Autodesk Fusion 360 part; units mm, degrees
(part 4 of 8)
sketch "F Mount Holes" plane through (-20.5061, -20.5061, 0) normal (0.707107, 0.707107, 0) x (0, 0, 1) in component "F Metal Hub Adapter"
  circle A0 centre (22.6274, 22.6274) radius 2.15
  circle A1 centre (-22.6274, 22.6274) radius 2.15
  circle A2 centre (-22.6274, -22.6274) radius 2.15
  circle A3 centre (22.6274, -22.6274) radius 2.15
  dimension "d983" = 22.6274
  dimension "d984" = 22.6274
  dimension "d985" = 4.3
  dimension "d986" = 22.6274
  dimension "d987" = 22.6274
  dimension "d988" = 4.3
  dimension "d989" = 22.6274
  dimension "d990" = 22.6274
  dimension "d991" = 4.3
  dimension "d992" = 22.6274
  dimension "d993" = 22.6274
  dimension "d994" = 4.3
  measures "d983" horizontal distance of origin A0.centre
  measures "d984" vertical distance of origin A0.centre
  measures "d985" diameter of A0
  measures "d986" horizontal distance of origin A1.centre
  measures "d987" vertical distance of origin A1.centre
  measures "d988" diameter of A1
  measures "d989" horizontal distance of origin A2.centre
  measures "d990" vertical distance of origin A2.centre
  measures "d991" diameter of A2
  measures "d992" horizontal distance of origin A3.centre
  measures "d993" vertical distance of origin A3.centre
  measures "d994" diameter of A3
extrude "F Four Mount Holes" cut sketch "F Mount Holes" along normal blind 6 bodies 10 in component "F Metal Hub Adapter"
sketch "F Compression Sleeve Holes" plane through (-20.5061, -20.5061, 0) normal (0.707107, 0.707107, 0) x (0, 0, 1) in component "F Metal Hub Adapter"
  circle A0 centre (11.3137, 0) radius 4.1
  line L0 (0, 0) -> (11.3137, 0) construction
  circle A1 centre (0, 11.3137) radius 4.1
  line L1 (0, 0) -> (0, 11.3137) construction
  circle A2 centre (-11.3137, 0) radius 4.1
  line L2 (0, 0) -> (-11.3137, 0) construction
  circle A3 centre (0, -11.3137) radius 4.1
  line L3 (0, 0) -> (0, -11.3137) construction
  dimension "d997" = 11.3137
  dimension "d998" = 8.2
  dimension "d999" = 11.3137
  dimension "d1000" = 8.2
  dimension "d1001" = 11.3137
  dimension "d1002" = 8.2
  dimension "d1003" = 11.3137
  dimension "d1004" = 8.2
  constraint horizontal L0
  constraint vertical L1
  constraint horizontal L2
  constraint vertical L3
  measures "d997" distance of L0.start A0.centre
  measures "d998" diameter of A0
  measures "d999" distance of L0.start A1.centre
  measures "d1000" diameter of A1
  measures "d1002" diameter of A2
  measures "d1003" distance of L0.start A3.centre
  measures "d1004" diameter of A3
extrude "F Four Sleeve Seats" cut sketch "F Compression Sleeve Holes" along normal blind 6 bodies 10 in component "F Metal Hub Adapter"
chamfer "F Pilot Lead In" distance 0.4 angle 45 1 edges at (-21.2418, -8.4567, -23.3082) tangent chain off on bodies 10 in component "F Metal Hub Adapter"
chamfer "F Bed Edge Relief" distance 0.3 angle 45 1 edges at (-30.2227, -10.7895, -35.4284) tangent chain off on bodies 10 in component "F Metal Hub Adapter"
ref_plane "WorkPlane1" through (0.3536, 0.3536, 12.125) normal (0.707107, 0.707107, 0) x (0, 0, 1) in component "REF Two 608 Bearings"
sketch "Front 608 sketch" plane through (0.3536, 0.3536, 0) normal (0.707107, 0.707107, 0) x (0, 0, 1) in component "REF Two 608 Bearings"
  circle A0 centre (0, 0) radius 11
  circle A1 centre (0, 0) radius 4
  dimension "d1011" = 22
  dimension "d1012" = 8
  measures "d1011" diameter of A0
  measures "d1012" diameter of A1
extrude "Front 608" add sketch "Front 608 sketch" along normal blind 7 separate body makes body 11 in component "REF Two 608 Bearings"
ref_plane "WorkPlane2" through (18.1019, 18.1019, 12.125) normal (0.707107, 0.707107, 0) x (0, 0, 1) in component "REF Two 608 Bearings"
sketch "Rear 608 sketch" plane through (18.1019, 18.1019, 0) normal (0.707107, 0.707107, 0) x (0, 0, 1) in component "REF Two 608 Bearings"
  circle A0 centre (0, 0) radius 11
  circle A1 centre (0, 0) radius 4
  dimension "d1017" = 22
  dimension "d1018" = 8
  measures "d1017" diameter of A0
  measures "d1018" diameter of A1
extrude "Rear 608" add sketch "Rear 608 sketch" along normal blind 7 separate body makes body 12 in component "REF Two 608 Bearings"
ref_plane "WorkPlane1" through (-16.9706, -16.9706, 12.125) normal (0.707107, 0.707107, 0) x (0, 0, 1) in component "REF Steel Shaft 8 x 60"
sketch "Metal Shaft sketch" plane through (-16.9706, -16.9706, 0) normal (0.707107, 0.707107, 0) x (0, 0, 1) in component "REF Steel Shaft 8 x 60"
  circle A0 centre (0, 0) radius 4
  dimension "d1023" = 8
  measures "d1023" diameter of A0
extrude "Metal Shaft" add sketch "Metal Shaft sketch" along normal blind 60 separate body makes body 13 in component "REF Steel Shaft 8 x 60"
ref_plane "WorkPlane1" through (-2.4749, -2.4749, 12.125) normal (0.707107, 0.707107, 0) x (0, 0, 1) in component "REF Inner Ring Spacers"
sketch "Front Inner Ring Spacer sketch" plane through (-2.4749, -2.4749, 0) normal (0.707107, 0.707107, 0) x (0, 0, 1) in component "REF Inner Ring Spacers"
  circle A0 centre (0, 0) radius 5
  circle A1 centre (0, 0) radius 4
  dimension "d1028" = 10
  dimension "d1029" = 8
  measures "d1028" diameter of A0
  measures "d1029" diameter of A1
extrude "Front Inner Ring Spacer" add sketch "Front Inner Ring Spacer sketch" along normal blind 4 separate body makes body 14 in component "REF Inner Ring Spacers"
ref_plane "WorkPlane2" through (5.3033, 5.3033, 12.125) normal (0.707107, 0.707107, 0) x (0, 0, 1) in component "REF Inner Ring Spacers"
sketch "Rear Inner Ring Spacer sketch" plane through (5.3033, 5.3033, 0) normal (0.707107, 0.707107, 0) x (0, 0, 1) in component "REF Inner Ring Spacers"
  circle A0 centre (0, 0) radius 5
  circle A1 centre (0, 0) radius 4
  dimension "d1034" = 10
  dimension "d1035" = 8
  measures "d1034" diameter of A0
  measures "d1035" diameter of A1
extrude "Rear Inner Ring Spacer" add sketch "Rear Inner Ring Spacer sketch" along normal blind 4 separate body makes body 15 in component "REF Inner Ring Spacers"
ref_plane "WorkPlane1" through (-8.8388, -8.8388, 12.125) normal (0.707107, 0.707107, 0) x (0, 0, 1) in component "REF Split Collar Envelopes"
sketch "Front Collar Maximum Envelope sketch" plane through (-8.8388, -8.8388, 0) normal (0.707107, 0.707107, 0) x (0, 0, 1) in component "REF Split Collar Envelopes"
  circle A0 centre (0, 0) radius 11.2
  circle A1 centre (0, 0) radius 4
  dimension "d1040" = 22.4
  dimension "d1041" = 8
  measures "d1040" diameter of A0
  measures "d1041" diameter of A1
extrude "Front Collar Maximum Envelope" add sketch "Front Collar Maximum Envelope sketch" along normal blind 9 separate body makes body 16 in component "REF Split Collar Envelopes"
ref_plane "WorkPlane2" through (8.1317, 8.1317, 12.125) normal (0.707107, 0.707107, 0) x (0, 0, 1) in component "REF Split Collar Envelopes"
sketch "Rear Collar Maximum Envelope sketch" plane through (8.1317, 8.1317, 0) normal (0.707107, 0.707107, 0) x (0, 0, 1) in component "REF Split Collar Envelopes"
  circle A0 centre (0, 0) radius 11.2
  circle A1 centre (0, 0) radius 4
  dimension "d1046" = 22.4
  dimension "d1047" = 8
  measures "d1046" diameter of A0
  measures "d1047" diameter of A1
extrude "Rear Collar Maximum Envelope" add sketch "Rear Collar Maximum Envelope sketch" along normal blind 9 separate body makes body 17 in component "REF Split Collar Envelopes"
ref_plane "WorkPlane1" through (0, 0, 12.125) normal (0.707107, 0.707107, 0) x (0, 0, 1) in component "REF Metal Support Spacers"
sketch "Spacer Pattern Axis" plane through (0, 0, 0) normal (0.707107, 0.707107, 0) x (0, 0, 1) in component "REF Metal Support Spacers"
  circle A0 centre (0, 0) radius 0.5
  dimension "d1052" = 1
  measures "d1052" diameter of A0
ref_plane "WorkPlane2" through (7.4953, 7.4953, 12.125) normal (0.707107, 0.707107, 0) x (0, 0, 1) in component "REF Metal Support Spacers"
sketch "Support Spacer OD" plane through (7.4953, 7.4953, 0) normal (0.707107, 0.707107, 0) x (0, 0, 1) in component "REF Metal Support Spacers"
  line L0 (0, 0) -> (17, 0) construction
  circle A0 centre (17, 0) radius 3
  circle A1 centre (17, 0) radius 1.6
  dimension "d1055" = 17
  dimension "d1056" = 6
  dimension "d1057" = 3.2
  constraint horizontal L0
  measures "d1055" distance of L0.start L0.end
  measures "d1056" diameter of A0
  measures "d1057" diameter of A1
extrude "Metal Standoff 12 mm" add sketch "Support Spacer OD" along normal blind 12 separate body makes body 18 in component "REF Metal Support Spacers"
pattern_circular "Three Metal Standoffs" count 3 over 360 about axis through (0, 0, 0) along (0.707107, 0.707107, 0) of "Metal Standoff 12 mm" makes body 19 at (22.6677, -2.0202, -9.7339) makes body 20 at (0.9599, 25.3445, -10.1276) in component "REF Metal Support Spacers"
ref_plane "WorkPlane1" through (-20.5061, -20.5061, 12.125) normal (0.707107, 0.707107, 0) x (0, 0, 1) in component "REF Hub Compression Sleeves"
sketch "Sleeve 1 Outer" plane through (-20.5061, -20.5061, 0) normal (0.707107, 0.707107, 0) x (0, 0, 1) in component "REF Hub Compression Sleeves"
  circle A0 centre (11.3137, 0) radius 4
  line L0 (0, 0) -> (11.3137, 0) construction
  circle A1 centre (11.3137, 0) radius 2.15
  dimension "d1064" = 11.3137
  dimension "d1065" = 8
  dimension "d1066" = 4.3
  constraint horizontal L0
  measures "d1064" distance of L0.start A0.centre
  measures "d1065" diameter of A0
  measures "d1066" diameter of A1
extrude "Sleeve 1" add sketch "Sleeve 1 Outer" along normal blind 6 separate body makes body 21 in component "REF Hub Compression Sleeves"
ref_plane "WorkPlane2" through (-20.5061, -20.5061, 12.125) normal (0.707107, 0.707107, 0) x (0, 0, 1) in component "REF Hub Compression Sleeves"
sketch "Sleeve 2 Outer" plane through (-20.5061, -20.5061, 0) normal (0.707107, 0.707107, 0) x (0, 0, 1) in component "REF Hub Compression Sleeves"
  circle A0 centre (0, 11.3137) radius 4
  line L0 (0, 0) -> (0, 11.3137) construction
  circle A1 centre (0, 11.3137) radius 2.15
  dimension "d1071" = 11.3137
  dimension "d1072" = 8
  dimension "d1073" = 4.3
  constraint vertical L0
  measures "d1071" distance of L0.start A0.centre
  measures "d1072" diameter of A0
  measures "d1073" diameter of A1
extrude "Sleeve 2" add sketch "Sleeve 2 Outer" along normal blind 6 separate body makes body 22 in component "REF Hub Compression Sleeves"
ref_plane "WorkPlane3" through (-20.5061, -20.5061, 12.125) normal (0.707107, 0.707107, 0) x (0, 0, 1) in component "REF Hub Compression Sleeves"
sketch "Sleeve 3 Outer" plane through (-20.5061, -20.5061, 0) normal (0.707107, 0.707107, 0) x (0, 0, 1) in component "REF Hub Compression Sleeves"
  circle A0 centre (-11.3137, 0) radius 4
  line L0 (0, 0) -> (-11.3137, 0) construction
  circle A1 centre (-11.3137, 0) radius 2.15
  dimension "d1078" = 11.3137
  dimension "d1079" = 8
  dimension "d1080" = 4.3
  constraint horizontal L0
  measures "d1078" distance of L0.start A0.centre
  measures "d1079" diameter of A0
  measures "d1080" diameter of A1
extrude "Sleeve 3" add sketch "Sleeve 3 Outer" along normal blind 6 separate body makes body 23 in component "REF Hub Compression Sleeves"
ref_plane "WorkPlane4" through (-20.5061, -20.5061, 12.125) normal (0.707107, 0.707107, 0) x (0, 0, 1) in component "REF Hub Compression Sleeves"
sketch "Sleeve 4 Outer" plane through (-20.5061, -20.5061, 0) normal (0.707107, 0.707107, 0) x (0, 0, 1) in component "REF Hub Compression Sleeves"
  circle A0 centre (0, -11.3137) radius 4
  line L0 (0, 0) -> (0, -11.3137) construction
  circle A1 centre (0, -11.3137) radius 2.15
  dimension "d1085" = 11.3137
  dimension "d1086" = 8
  dimension "d1087" = 4.3
  constraint vertical L0
  measures "d1085" distance of L0.start A0.centre
  measures "d1086" diameter of A0
  measures "d1087" diameter of A1
extrude "Sleeve 4" add sketch "Sleeve 4 Outer" along normal blind 6 separate body makes body 24 in component "REF Hub Compression Sleeves"
ref_plane "WorkPlane1" through (-16.2635, -16.2635, 12.125) normal (0.707107, 0.707107, 0) x (0, 0, 1) in component "REF Sonic Hub Envelope"
sketch "Sonic Hub Body sketch" plane through (-16.2635, -16.2635, 0) normal (0.707107, 0.707107, 0) x (0, 0, 1) in component "REF Sonic Hub Envelope"
  circle A0 centre (0, 0) radius 16
  circle A1 centre (0, 0) radius 4
  dimension "d1092" = 32
  dimension "d1093" = 8
  measures "d1092" diameter of A0
  measures "d1093" diameter of A1
extrude "Sonic Hub Body" add sketch "Sonic Hub Body sketch" along normal blind 8 separate body makes body 25 in component "REF Sonic Hub Envelope"
ref_plane "WorkPlane2" through (-10.6066, -10.6066, 12.125) normal (0.707107, 0.707107, 0) x (0, 0, 1) in component "REF Sonic Hub Envelope"
sketch "Sonic Hub Pilot sketch" plane through (-10.6066, -10.6066, 0) normal (0.707107, 0.707107, 0) x (0, 0, 1) in component "REF Sonic Hub Envelope"
  circle A0 centre (0, 0) radius 7
  circle A1 centre (0, 0) radius 4
  dimension "d1098" = 14
  dimension "d1099" = 8
  measures "d1098" diameter of A0
  measures "d1099" diameter of A1
extrude "Sonic Hub Pilot" add sketch "Sonic Hub Pilot sketch" along normal blind 2 bodies 25 in component "REF Sonic Hub Envelope"
ref_plane "WorkPlane3" through (-16.2635, -16.2635, 12.125) normal (0.707107, 0.707107, 0) x (0, 0, 1) in component "REF Sonic Hub Envelope"
sketch "Hub M4 Thread Envelopes" plane through (-16.2635, -16.2635, 0) normal (0.707107, 0.707107, 0) x (0, 0, 1) in component "REF Sonic Hub Envelope"
  circle A0 centre (11.3137, 0) radius 2.15
  line L0 (0, 0) -> (11.3137, 0) construction
  circle A1 centre (0, 11.3137) radius 2.15
  line L1 (0, 0) -> (0, 11.3137) construction
  circle A2 centre (-11.3137, 0) radius 2.15
  line L2 (0, 0) -> (-11.3137, 0) construction
  circle A3 centre (0, -11.3137) radius 2.15
  line L3 (0, 0) -> (0, -11.3137) construction
  dimension "d1104" = 11.3137
  dimension "d1105" = 4.3
  dimension "d1106" = 11.3137
  dimension "d1107" = 4.3
  dimension "d1108" = 11.3137
  dimension "d1109" = 4.3
  dimension "d1110" = 11.3137
  dimension "d1111" = 4.3
  constraint horizontal L0
  constraint vertical L1
  constraint horizontal L2
  constraint vertical L3
  measures "d1104" distance of L0.start A0.centre
  measures "d1105" diameter of A0
  measures "d1106" distance of L0.start A1.centre
  measures "d1107" diameter of A1
  measures "d1109" diameter of A2
  measures "d1110" distance of L0.start A3.centre
  measures "d1111" diameter of A3
extrude "Hub Nominal Thread Passages" cut sketch "Hub M4 Thread Envelopes" along normal blind 8 bodies 25 in component "REF Sonic Hub Envelope"
ref_plane "WorkPlane1" through (-21.2132, -21.2132, 12.125) normal (0.707107, 0.707107, 0) x (0, 0, 1) in component "REF M4 Hub Screws"
sketch "Hub Screw 1 Profile" plane through (-21.2132, -21.2132, 0) normal (0.707107, 0.707107, 0) x (0, 0, 1) in component "REF M4 Hub Screws"
  circle A0 centre (11.3137, 0) radius 2
  line L0 (0, 0) -> (11.3137, 0) construction
  dimension "d1116" = 11.3137
  dimension "d1117" = 4
  constraint horizontal L0
  measures "d1116" distance of L0.start A0.centre
  measures "d1117" diameter of A0
extrude "Hub Screw 1" add sketch "Hub Screw 1 Profile" along normal blind 12 separate body makes body 26 in component "REF M4 Hub Screws"
ref_plane "WorkPlane2" through (-24.0416, -24.0416, 12.125) normal (0.707107, 0.707107, 0) x (0, 0, 1) in component "REF M4 Hub Screws"
sketch "Hub Screw Head 1 Profile" plane through (-24.0416, -24.0416, 0) normal (0.707107, 0.707107, 0) x (0, 0, 1) in component "REF M4 Hub Screws"
  circle A0 centre (11.3137, 0) radius 3.5
  line L0 (0, 0) -> (11.3137, 0) construction
  dimension "d1122" = 11.3137
  dimension "d1123" = 7
  constraint horizontal L0
  measures "d1122" distance of L0.start A0.centre
  measures "d1123" diameter of A0
extrude "Hub Screw Head 1" add sketch "Hub Screw Head 1 Profile" along normal blind 4 separate body makes body 27 in component "REF M4 Hub Screws"
ref_plane "WorkPlane3" through (-21.2132, -21.2132, 12.125) normal (0.707107, 0.707107, 0) x (0, 0, 1) in component "REF M4 Hub Screws"
sketch "Hub Washer 1 Outer" plane through (-21.2132, -21.2132, 0) normal (0.707107, 0.707107, 0) x (0, 0, 1) in component "REF M4 Hub Screws"
  circle A0 centre (11.3137, 0) radius 6
  line L0 (0, 0) -> (11.3137, 0) construction
  circle A1 centre (11.3137, 0) radius 2.15
  dimension "d1128" = 11.3137
  dimension "d1129" = 12
  dimension "d1130" = 4.3
  constraint horizontal L0
  measures "d1128" distance of L0.start A0.centre
  measures "d1129" diameter of A0
  measures "d1130" diameter of A1
extrude "Hub Washer 1" add sketch "Hub Washer 1 Outer" along normal blind 1 separate body makes body 28 in component "REF M4 Hub Screws"
ref_plane "WorkPlane4" through (-21.2132, -21.2132, 12.125) normal (0.707107, 0.707107, 0) x (0, 0, 1) in component "REF M4 Hub Screws"
sketch "Hub Screw 2 Profile" plane through (-21.2132, -21.2132, 0) normal (0.707107, 0.707107, 0) x (0, 0, 1) in component "REF M4 Hub Screws"
  circle A0 centre (0, 11.3137) radius 2
  line L0 (0, 0) -> (0, 11.3137) construction
  dimension "d1135" = 11.3137
  dimension "d1136" = 4
  constraint vertical L0
  measures "d1135" distance of L0.start A0.centre
  measures "d1136" diameter of A0
extrude "Hub Screw 2" add sketch "Hub Screw 2 Profile" along normal blind 12 separate body makes body 29 in component "REF M4 Hub Screws"
ref_plane "WorkPlane5" through (-24.0416, -24.0416, 12.125) normal (0.707107, 0.707107, 0) x (0, 0, 1) in component "REF M4 Hub Screws"
sketch "Hub Screw Head 2 Profile" plane through (-24.0416, -24.0416, 0) normal (0.707107, 0.707107, 0) x (0, 0, 1) in component "REF M4 Hub Screws"
  circle A0 centre (0, 11.3137) radius 3.5
  line L0 (0, 0) -> (0, 11.3137) construction
  dimension "d1141" = 11.3137
  dimension "d1142" = 7
  constraint vertical L0
  measures "d1141" distance of L0.start A0.centre
  measures "d1142" diameter of A0
extrude "Hub Screw Head 2" add sketch "Hub Screw Head 2 Profile" along normal blind 4 separate body makes body 30 in component "REF M4 Hub Screws"
ref_plane "WorkPlane6" through (-21.2132, -21.2132, 12.125) normal (0.707107, 0.707107, 0) x (0, 0, 1) in component "REF M4 Hub Screws"
sketch "Hub Washer 2 Outer" plane through (-21.2132, -21.2132, 0) normal (0.707107, 0.707107, 0) x (0, 0, 1) in component "REF M4 Hub Screws"
  circle A0 centre (0, 11.3137) radius 6
  line L0 (0, 0) -> (0, 11.3137) construction
  circle A1 centre (0, 11.3137) radius 2.15
  dimension "d1147" = 11.3137
  dimension "d1148" = 12
  dimension "d1149" = 4.3
  constraint vertical L0
  measures "d1147" distance of L0.start A0.centre
  measures "d1148" diameter of A0
  measures "d1149" diameter of A1
extrude "Hub Washer 2" add sketch "Hub Washer 2 Outer" along normal blind 1 separate body makes body 31 in component "REF M4 Hub Screws"
ref_plane "WorkPlane7" through (-21.2132, -21.2132, 12.125) normal (0.707107, 0.707107, 0) x (0, 0, 1) in component "REF M4 Hub Screws"
sketch "Hub Screw 3 Profile" plane through (-21.2132, -21.2132, 0) normal (0.707107, 0.707107, 0) x (0, 0, 1) in component "REF M4 Hub Screws"
  circle A0 centre (-11.3137, 0) radius 2
  line L0 (0, 0) -> (-11.3137, 0) construction
  dimension "d1154" = 11.3137
  dimension "d1155" = 4
  constraint horizontal L0
  measures "d1154" distance of L0.start A0.centre
  measures "d1155" diameter of A0
extrude "Hub Screw 3" add sketch "Hub Screw 3 Profile" along normal blind 12 separate body makes body 32 in component "REF M4 Hub Screws"
ref_plane "WorkPlane8" through (-24.0416, -24.0416, 12.125) normal (0.707107, 0.707107, 0) x (0, 0, 1) in component "REF M4 Hub Screws"
sketch "Hub Screw Head 3 Profile" plane through (-24.0416, -24.0416, 0) normal (0.707107, 0.707107, 0) x (0, 0, 1) in component "REF M4 Hub Screws"
  circle A0 centre (-11.3137, 0) radius 3.5
  line L0 (0, 0) -> (-11.3137, 0) construction
  dimension "d1160" = 11.3137
  dimension "d1161" = 7
  constraint horizontal L0
  measures "d1160" distance of L0.start A0.centre
  measures "d1161" diameter of A0
extrude "Hub Screw Head 3" add sketch "Hub Screw Head 3 Profile" along normal blind 4 separate body makes body 33 in component "REF M4 Hub Screws"
ref_plane "WorkPlane9" through (-21.2132, -21.2132, 12.125) normal (0.707107, 0.707107, 0) x (0, 0, 1) in component "REF M4 Hub Screws"
sketch "Hub Washer 3 Outer" plane through (-21.2132, -21.2132, 0) normal (0.707107, 0.707107, 0) x (0, 0, 1) in component "REF M4 Hub Screws"
  circle A0 centre (-11.3137, 0) radius 6
  line L0 (0, 0) -> (-11.3137, 0) construction
  circle A1 centre (-11.3137, 0) radius 2.15
  dimension "d1166" = 11.3137
  dimension "d1167" = 12
  dimension "d1168" = 4.3
  constraint horizontal L0
  measures "d1166" distance of L0.start A0.centre
  measures "d1167" diameter of A0
  measures "d1168" diameter of A1
extrude "Hub Washer 3" add sketch "Hub Washer 3 Outer" along normal blind 1 separate body makes body 34 in component "REF M4 Hub Screws"
ref_plane "WorkPlane10" through (-21.2132, -21.2132, 12.125) normal (0.707107, 0.707107, 0) x (0, 0, 1) in component "REF M4 Hub Screws"
sketch "Hub Screw 4 Profile" plane through (-21.2132, -21.2132, 0) normal (0.707107, 0.707107, 0) x (0, 0, 1) in component "REF M4 Hub Screws"
  circle A0 centre (0, -11.3137) radius 2
  line L0 (0, 0) -> (0, -11.3137) construction
  dimension "d1173" = 11.3137
  dimension "d1174" = 4
  constraint vertical L0
  measures "d1173" distance of L0.start A0.centre
  measures "d1174" diameter of A0
extrude "Hub Screw 4" add sketch "Hub Screw 4 Profile" along normal blind 12 separate body makes body 35 in component "REF M4 Hub Screws"
ref_plane "WorkPlane11" through (-24.0416, -24.0416, 12.125) normal (0.707107, 0.707107, 0) x (0, 0, 1) in component "REF M4 Hub Screws"
sketch "Hub Screw Head 4 Profile" plane through (-24.0416, -24.0416, 0) normal (0.707107, 0.707107, 0) x (0, 0, 1) in component "REF M4 Hub Screws"
  circle A0 centre (0, -11.3137) radius 3.5
  line L0 (0, 0) -> (0, -11.3137) construction
  dimension "d1179" = 11.3137
  dimension "d1180" = 7
  constraint vertical L0
  measures "d1179" distance of L0.start A0.centre
  measures "d1180" diameter of A0
extrude "Hub Screw Head 4" add sketch "Hub Screw Head 4 Profile" along normal blind 4 separate body makes body 36 in component "REF M4 Hub Screws"
ref_plane "WorkPlane12" through (-21.2132, -21.2132, 12.125) normal (0.707107, 0.707107, 0) x (0, 0, 1) in component "REF M4 Hub Screws"
sketch "Hub Washer 4 Outer" plane through (-21.2132, -21.2132, 0) normal (0.707107, 0.707107, 0) x (0, 0, 1) in component "REF M4 Hub Screws"
  circle A0 centre (0, -11.3137) radius 6
  line L0 (0, 0) -> (0, -11.3137) construction
  circle A1 centre (0, -11.3137) radius 2.15
  dimension "d1185" = 11.3137
  dimension "d1186" = 12
  dimension "d1187" = 4.3
  constraint vertical L0
  measures "d1185" distance of L0.start A0.centre
  measures "d1186" diameter of A0
  measures "d1187" diameter of A1
extrude "Hub Washer 4" add sketch "Hub Washer 4 Outer" along normal blind 1 separate body makes body 37 in component "REF M4 Hub Screws"
ref_plane "WorkPlane1" through (-21.2132, -21.2132, 12.125) normal (0.707107, 0.707107, 0) x (0, 0, 1) in component "REF M4 Adapter Fasteners"
sketch "Adapter Screw 1 Profile" plane through (-21.2132, -21.2132, 0) normal (0.707107, 0.707107, 0) x (0, 0, 1) in component "REF M4 Adapter Fasteners"
  circle A0 centre (22.6274, 22.6274) radius 2
  dimension "d1192" = 22.6274
  dimension "d1193" = 22.6274
  dimension "d1194" = 4
  measures "d1192" horizontal distance of origin A0.centre
  measures "d1193" vertical distance of origin A0.centre
  measures "d1194" diameter of A0
extrude "Adapter Screw 1" add sketch "Adapter Screw 1 Profile" along normal blind 30 separate body makes body 38 in component "REF M4 Adapter Fasteners"
ref_plane "WorkPlane2" through (-24.0416, -24.0416, 12.125) normal (0.707107, 0.707107, 0) x (0, 0, 1) in component "REF M4 Adapter Fasteners"
sketch "Adapter Screw Head 1 Profile" plane through (-24.0416, -24.0416, 0) normal (0.707107, 0.707107, 0) x (0, 0, 1) in component "REF M4 Adapter Fasteners"
  circle A0 centre (22.6274, 22.6274) radius 3.5
  dimension "d1199" = 22.6274
  dimension "d1200" = 22.6274
  dimension "d1201" = 7
  measures "d1199" horizontal distance of origin A0.centre
  measures "d1200" vertical distance of origin A0.centre
  measures "d1201" diameter of A0
extrude "Adapter Screw Head 1" add sketch "Adapter Screw Head 1 Profile" along normal blind 4 separate body makes body 39 in component "REF M4 Adapter Fasteners"
ref_plane "WorkPlane3" through (-21.2132, -21.2132, 12.125) normal (0.707107, 0.707107, 0) x (0, 0, 1) in component "REF M4 Adapter Fasteners"
sketch "Adapter Washer 1 Outer" plane through (-21.2132, -21.2132, 0) normal (0.707107, 0.707107, 0) x (0, 0, 1) in component "REF M4 Adapter Fasteners"
  circle A0 centre (22.6274, 22.6274) radius 4.5
  circle A1 centre (22.6274, 22.6274) radius 2.15
  dimension "d1206" = 22.6274
  dimension "d1207" = 22.6274
  dimension "d1208" = 9
  dimension "d1209" = 4.3
  measures "d1206" horizontal distance of origin A0.centre
  measures "d1207" vertical distance of origin A0.centre
  measures "d1208" diameter of A0
  measures "d1209" diameter of A1
extrude "Adapter Washer 1" add sketch "Adapter Washer 1 Outer" along normal blind 1 separate body makes body 40 in component "REF M4 Adapter Fasteners"
ref_plane "WorkPlane4" through (-3.182, -3.182, 12.125) normal (0.707107, 0.707107, 0) x (0, 0, 1) in component "REF M4 Adapter Fasteners"
sketch "Adapter Nut Hex 1" plane through (-3.182, -3.182, 0) normal (0.707107, 0.707107, 0) x (0, 0, 1) in component "REF M4 Adapter Fasteners"
  circle A0 centre (22.6274, 22.6274) radius 4.0415 construction
  line L0 (26.6689, 22.6274) -> (24.6481, 26.1274)
  line L1 (24.6481, 26.1274) -> (20.6067, 26.1274)
  line L2 (20.6067, 26.1274) -> (18.586, 22.6274)
  line L3 (18.586, 22.6274) -> (20.6067, 19.1274)
  line L4 (20.6067, 19.1274) -> (24.6481, 19.1274)
  line L5 (24.6481, 19.1274) -> (26.6689, 22.6274)
  dimension "d1214" = 22.6274
  dimension "d1215" = 22.6274
  dimension "d1216" = 8.0829
  constraint coincident A0 L0.start
  constraint coincident A0 L0.end
  constraint coincident A0 L1.end
  constraint coincident A0 L2.end
  constraint coincident A0 L3.end
  constraint coincident A0 L4.end
  constraint equal L0 L1
  constraint equal L0 L2
  constraint equal L0 L3
  constraint equal L0 L4
  constraint equal L0 L5
  constraint horizontal L1
  measures "d1214" horizontal distance of origin A0.centre
  measures "d1215" vertical distance of origin A0.centre
  measures "d1216" diameter of A0
extrude "Adapter Nut 1" add sketch "Adapter Nut Hex 1" along normal blind 3.2 separate body makes body 41 in component "REF M4 Adapter Fasteners"
sketch "Nut Thread Clearance 1" plane through (-3.182, -3.182, 0) normal (0.707107, 0.707107, 0) x (0, 0, 1) in component "REF M4 Adapter Fasteners"
  circle A0 centre (22.6274, 22.6274) radius 2.15
  dimension "d1219" = 22.6274
  dimension "d1220" = 22.6274
  dimension "d1221" = 4.3
  measures "d1219" horizontal distance of origin A0.centre
  measures "d1220" vertical distance of origin A0.centre
  measures "d1221" diameter of A0
extrude "Nut Bore 1" cut sketch "Nut Thread Clearance 1" along normal blind 3.2 bodies 41 in component "REF M4 Adapter Fasteners"
ref_plane "WorkPlane5" through (-21.2132, -21.2132, 12.125) normal (0.707107, 0.707107, 0) x (0, 0, 1) in component "REF M4 Adapter Fasteners"
sketch "Adapter Screw 2 Profile" plane through (-21.2132, -21.2132, 0) normal (0.707107, 0.707107, 0) x (0, 0, 1) in component "REF M4 Adapter Fasteners"
  circle A0 centre (-22.6274, 22.6274) radius 2
  dimension "d1226" = 22.6274
  dimension "d1227" = 22.6274
  dimension "d1228" = 4
  measures "d1226" horizontal distance of origin A0.centre
  measures "d1227" vertical distance of origin A0.centre
  measures "d1228" diameter of A0
extrude "Adapter Screw 2" add sketch "Adapter Screw 2 Profile" along normal blind 30 separate body makes body 42 in component "REF M4 Adapter Fasteners"
ref_plane "WorkPlane6" through (-24.0416, -24.0416, 12.125) normal (0.707107, 0.707107, 0) x (0, 0, 1) in component "REF M4 Adapter Fasteners"
sketch "Adapter Screw Head 2 Profile" plane through (-24.0416, -24.0416, 0) normal (0.707107, 0.707107, 0) x (0, 0, 1) in component "REF M4 Adapter Fasteners"
  circle A0 centre (-22.6274, 22.6274) radius 3.5
  dimension "d1233" = 22.6274
  dimension "d1234" = 22.6274
  dimension "d1235" = 7
  measures "d1233" horizontal distance of origin A0.centre
  measures "d1234" vertical distance of origin A0.centre
  measures "d1235" diameter of A0
extrude "Adapter Screw Head 2" add sketch "Adapter Screw Head 2 Profile" along normal blind 4 separate body makes body 43 in component "REF M4 Adapter Fasteners"
ref_plane "WorkPlane7" through (-21.2132, -21.2132, 12.125) normal (0.707107, 0.707107, 0) x (0, 0, 1) in component "REF M4 Adapter Fasteners"
sketch "Adapter Washer 2 Outer" plane through (-21.2132, -21.2132, 0) normal (0.707107, 0.707107, 0) x (0, 0, 1) in component "REF M4 Adapter Fasteners"
  circle A0 centre (-22.6274, 22.6274) radius 4.5
  circle A1 centre (-22.6274, 22.6274) radius 2.15
  dimension "d1240" = 22.6274
  dimension "d1241" = 22.6274
  dimension "d1242" = 9
  dimension "d1243" = 4.3
  measures "d1240" horizontal distance of origin A0.centre
  measures "d1241" vertical distance of origin A0.centre
  measures "d1242" diameter of A0
  measures "d1243" diameter of A1
extrude "Adapter Washer 2" add sketch "Adapter Washer 2 Outer" along normal blind 1 separate body makes body 44 in component "REF M4 Adapter Fasteners"
ref_plane "WorkPlane8" through (-3.182, -3.182, 12.125) normal (0.707107, 0.707107, 0) x (0, 0, 1) in component "REF M4 Adapter Fasteners"
sketch "Adapter Nut Hex 2" plane through (-3.182, -3.182, 0) normal (0.707107, 0.707107, 0) x (0, 0, 1) in component "REF M4 Adapter Fasteners"
  circle A0 centre (-22.6274, 22.6274) radius 4.0415 construction
  line L0 (-18.586, 22.6274) -> (-20.6067, 26.1274)
  line L1 (-20.6067, 26.1274) -> (-24.6481, 26.1274)
  line L2 (-24.6481, 26.1274) -> (-26.6689, 22.6274)
  line L3 (-26.6689, 22.6274) -> (-24.6481, 19.1274)
  line L4 (-24.6481, 19.1274) -> (-20.6067, 19.1274)
  line L5 (-20.6067, 19.1274) -> (-18.586, 22.6274)
  dimension "d1248" = 22.6274
  dimension "d1249" = 22.6274
  dimension "d1250" = 8.0829
  constraint coincident A0 L0.start
  constraint coincident A0 L0.end
  constraint coincident A0 L1.end
  constraint coincident A0 L2.end
  constraint coincident A0 L3.end
  constraint coincident A0 L4.end
  constraint equal L0 L1
  constraint equal L0 L2
  constraint equal L0 L3
  constraint equal L0 L4
  constraint equal L0 L5
  constraint horizontal L1
  measures "d1248" horizontal distance of origin A0.centre
  measures "d1249" vertical distance of origin A0.centre
  measures "d1250" diameter of A0
extrude "Adapter Nut 2" add sketch "Adapter Nut Hex 2" along normal blind 3.2 separate body makes body 45 in component "REF M4 Adapter Fasteners"
sketch "Nut Thread Clearance 2" plane through (-3.182, -3.182, 0) normal (0.707107, 0.707107, 0) x (0, 0, 1) in component "REF M4 Adapter Fasteners"
  circle A0 centre (-22.6274, 22.6274) radius 2.15
  dimension "d1253" = 22.6274
  dimension "d1254" = 22.6274
  dimension "d1255" = 4.3
  measures "d1253" horizontal distance of origin A0.centre
  measures "d1254" vertical distance of origin A0.centre
  measures "d1255" diameter of A0
extrude "Nut Bore 2" cut sketch "Nut Thread Clearance 2" along normal blind 3.2 bodies 45 in component "REF M4 Adapter Fasteners"
ref_plane "WorkPlane9" through (-21.2132, -21.2132, 12.125) normal (0.707107, 0.707107, 0) x (0, 0, 1) in component "REF M4 Adapter Fasteners"
sketch "Adapter Screw 3 Profile" plane through (-21.2132, -21.2132, 0) normal (0.707107, 0.707107, 0) x (0, 0, 1) in component "REF M4 Adapter Fasteners"
  circle A0 centre (-22.6274, -22.6274) radius 2
  dimension "d1260" = 22.6274
  dimension "d1261" = 22.6274
  dimension "d1262" = 4
  measures "d1260" horizontal distance of origin A0.centre
  measures "d1261" vertical distance of origin A0.centre
  measures "d1262" diameter of A0
extrude "Adapter Screw 3" add sketch "Adapter Screw 3 Profile" along normal blind 30 separate body makes body 46 in component "REF M4 Adapter Fasteners"
ref_plane "WorkPlane10" through (-24.0416, -24.0416, 12.125) normal (0.707107, 0.707107, 0) x (0, 0, 1) in component "REF M4 Adapter Fasteners"
sketch "Adapter Screw Head 3 Profile" plane through (-24.0416, -24.0416, 0) normal (0.707107, 0.707107, 0) x (0, 0, 1) in component "REF M4 Adapter Fasteners"
  circle A0 centre (-22.6274, -22.6274) radius 3.5
  dimension "d1267" = 22.6274
  dimension "d1268" = 22.6274
  dimension "d1269" = 7
  measures "d1267" horizontal distance of origin A0.centre
  measures "d1268" vertical distance of origin A0.centre
  measures "d1269" diameter of A0
extrude "Adapter Screw Head 3" add sketch "Adapter Screw Head 3 Profile" along normal blind 4 separate body makes body 47 in component "REF M4 Adapter Fasteners"
ref_plane "WorkPlane11" through (-21.2132, -21.2132, 12.125) normal (0.707107, 0.707107, 0) x (0, 0, 1) in component "REF M4 Adapter Fasteners"
sketch "Adapter Washer 3 Outer" plane through (-21.2132, -21.2132, 0) normal (0.707107, 0.707107, 0) x (0, 0, 1) in component "REF M4 Adapter Fasteners"
  circle A0 centre (-22.6274, -22.6274) radius 4.5
  circle A1 centre (-22.6274, -22.6274) radius 2.15
  dimension "d1274" = 22.6274
  dimension "d1275" = 22.6274
  dimension "d1276" = 9
  dimension "d1277" = 4.3
  measures "d1274" horizontal distance of origin A0.centre
  measures "d1275" vertical distance of origin A0.centre
  measures "d1276" diameter of A0
  measures "d1277" diameter of A1
extrude "Adapter Washer 3" add sketch "Adapter Washer 3 Outer" along normal blind 1 separate body makes body 48 in component "REF M4 Adapter Fasteners"
ref_plane "WorkPlane12" through (-3.182, -3.182, 12.125) normal (0.707107, 0.707107, 0) x (0, 0, 1) in component "REF M4 Adapter Fasteners"
sketch "Adapter Nut Hex 3" plane through (-3.182, -3.182, 0) normal (0.707107, 0.707107, 0) x (0, 0, 1) in component "REF M4 Adapter Fasteners"
  circle A0 centre (-22.6274, -22.6274) radius 4.0415 construction
  line L0 (-18.586, -22.6274) -> (-20.6067, -19.1274)
  line L1 (-20.6067, -19.1274) -> (-24.6481, -19.1274)
  line L2 (-24.6481, -19.1274) -> (-26.6689, -22.6274)
  line L3 (-26.6689, -22.6274) -> (-24.6481, -26.1274)
  line L4 (-24.6481, -26.1274) -> (-20.6067, -26.1274)
  line L5 (-20.6067, -26.1274) -> (-18.586, -22.6274)
  dimension "d1282" = 22.6274
  dimension "d1283" = 22.6274
  dimension "d1284" = 8.0829
  constraint coincident A0 L0.start
  constraint coincident A0 L0.end
  constraint coincident A0 L1.end
  constraint coincident A0 L2.end
  constraint coincident A0 L3.end
  constraint coincident A0 L4.end
  constraint equal L0 L1
  constraint equal L0 L2
  constraint equal L0 L3
  constraint equal L0 L4
  constraint equal L0 L5
  constraint horizontal L1
  measures "d1282" horizontal distance of origin A0.centre
  measures "d1283" vertical distance of origin A0.centre
  measures "d1284" diameter of A0
extrude "Adapter Nut 3" add sketch "Adapter Nut Hex 3" along normal blind 3.2 separate body makes body 49 in component "REF M4 Adapter Fasteners"
sketch "Nut Thread Clearance 3" plane through (-3.182, -3.182, 0) normal (0.707107, 0.707107, 0) x (0, 0, 1) in component "REF M4 Adapter Fasteners"
  circle A0 centre (-22.6274, -22.6274) radius 2.15
  dimension "d1287" = 22.6274
  dimension "d1288" = 22.6274
  dimension "d1289" = 4.3
  measures "d1287" horizontal distance of origin A0.centre
  measures "d1288" vertical distance of origin A0.centre
  measures "d1289" diameter of A0
extrude "Nut Bore 3" cut sketch "Nut Thread Clearance 3" along normal blind 3.2 bodies 49 in component "REF M4 Adapter Fasteners"
ref_plane "WorkPlane13" through (-21.2132, -21.2132, 12.125) normal (0.707107, 0.707107, 0) x (0, 0, 1) in component "REF M4 Adapter Fasteners"
sketch "Adapter Screw 4 Profile" plane through (-21.2132, -21.2132, 0) normal (0.707107, 0.707107, 0) x (0, 0, 1) in component "REF M4 Adapter Fasteners"
  circle A0 centre (22.6274, -22.6274) radius 2
  dimension "d1294" = 22.6274
  dimension "d1295" = 22.6274
  dimension "d1296" = 4
  measures "d1294" horizontal distance of origin A0.centre
  measures "d1295" vertical distance of origin A0.centre
  measures "d1296" diameter of A0
extrude "Adapter Screw 4" add sketch "Adapter Screw 4 Profile" along normal blind 30 separate body makes body 50 in component "REF M4 Adapter Fasteners"
ref_plane "WorkPlane14" through (-24.0416, -24.0416, 12.125) normal (0.707107, 0.707107, 0) x (0, 0, 1) in component "REF M4 Adapter Fasteners"
sketch "Adapter Screw Head 4 Profile" plane through (-24.0416, -24.0416, 0) normal (0.707107, 0.707107, 0) x (0, 0, 1) in component "REF M4 Adapter Fasteners"
  circle A0 centre (22.6274, -22.6274) radius 3.5
  dimension "d1301" = 22.6274
  dimension "d1302" = 22.6274
  dimension "d1303" = 7
  measures "d1301" horizontal distance of origin A0.centre
  measures "d1302" vertical distance of origin A0.centre
  measures "d1303" diameter of A0
extrude "Adapter Screw Head 4" add sketch "Adapter Screw Head 4 Profile" along normal blind 4 separate body makes body 51 in component "REF M4 Adapter Fasteners"
ref_plane "WorkPlane15" through (-21.2132, -21.2132, 12.125) normal (0.707107, 0.707107, 0) x (0, 0, 1) in component "REF M4 Adapter Fasteners"